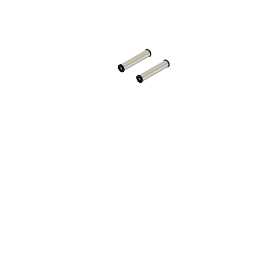
gripper_w_0.4 (Autodesk Fusion 360 archive; units mm, degrees)
design "supporto buchi finger"
part number: 2026-08-27-12-48-02-350
Autodesk Fusion 360 part; units mm, degrees
sketch "Sketch1" plane through (0, 0, 0) normal (0, 0, 1) x (1, 0, 0)
  circle A0 centre (5.3993, 52.9412) radius 2.25
  circle A1 centre (5.3993, 52.9412) radius 1.25
  circle A2 centre (5.3993, 52.9412) radius 1.25
  circle A3 centre (20.3993, 52.9411) radius 2.25
  circle A4 centre (20.3993, 52.9411) radius 1.25
  circle A5 centre (20.3993, 52.9411) radius 1.25
  dimension "d1154" = 4.5
  dimension "d1155" = 2.5
  dimension "d1156" = 4.5
  dimension "d1157" = 2.5
  constraint concentric A0 A1
  constraint concentric A1 A2
  constraint concentric A3 A4
  constraint concentric A3 A5
  measures "d1154" diameter of A0
  measures "d1155" diameter of A2
  measures "d1156" diameter of A3
  measures "d1157" diameter of A5
extrude "Extrude1" add sketch "Sketch1" along normal mid plane 22 makes body 1 at (7.6465, 52.829, 7.3333) makes body 2 at (18.1605, 52.7171, 7.3333)
